Autodesk Fusion 360 part; units mm, degrees
(part 6 of 7)
extrude "Washer (3)'" add sketch "Washer (2) (3)" along normal blind 0.4 separate body makes body 75 in component "HARDWARE | PCA M2x14 · unthreaded reference"
ref_plane "WorkPlane16" through (0, 0, 22.57) normal (0, 0, 1) x (1, 0, 0) in component "HARDWARE | PCA M2x14 · unthreaded reference"
sketch "Washer clearance (2) (3)" plane through (0, 0, 22.57) normal (0, 0, 1) x (1, 0, 0) in component "HARDWARE | PCA M2x14 · unthreaded reference"
  circle A0 centre (27.94, -25.525) radius 1.2
extrude "Washer clearance (3)'" cut sketch "Washer clearance (2) (3)" along normal blind 0.4 bodies 75 in component "HARDWARE | PCA M2x14 · unthreaded reference"
ref_plane "WorkPlane17" through (0, 0, 22.97) normal (0, 0, 1) x (1, 0, 0) in component "HARDWARE | PCA M2x14 · unthreaded reference"
sketch "Hex nut (2) (3)" plane through (0, 0, 22.97) normal (0, 0, 1) x (1, 0, 0) in component "HARDWARE | PCA M2x14 · unthreaded reference"
  line L0 (30.2494, -25.525) -> (29.0947, -23.525)
  line L1 (29.0947, -23.525) -> (26.7853, -23.525)
  line L2 (26.7853, -23.525) -> (25.6306, -25.525)
  line L3 (25.6306, -25.525) -> (26.7853, -27.525)
  line L4 (26.7853, -27.525) -> (29.0947, -27.525)
  line L5 (29.0947, -27.525) -> (30.2494, -25.525)
extrude "Hex nut (3)'" add sketch "Hex nut (2) (3)" along normal blind 1.6 separate body makes body 76 in component "HARDWARE | PCA M2x14 · unthreaded reference"
ref_plane "WorkPlane18" through (0, 0, 22.97) normal (0, 0, 1) x (1, 0, 0) in component "HARDWARE | PCA M2x14 · unthreaded reference"
sketch "Nut thread envelope clearance (2) (3)" plane through (0, 0, 22.97) normal (0, 0, 1) x (1, 0, 0) in component "HARDWARE | PCA M2x14 · unthreaded reference"
  circle A0 centre (27.94, -25.525) radius 1.15
extrude "Nut thread envelope clearance (3)'" cut sketch "Nut thread envelope clearance (2) (3)" along normal blind 1.6 bodies 76 in component "HARDWARE | PCA M2x14 · unthreaded reference"
ref_plane "WorkPlane19" through (0, 0, 12) normal (0, 0, 1) x (1, 0, 0) in component "HARDWARE | PCA M2x14 · unthreaded reference"
sketch "Bolt shank (3) (3)" plane through (0, 0, 12) normal (0, 0, 1) x (1, 0, 0) in component "HARDWARE | PCA M2x14 · unthreaded reference"
  circle A0 centre (27.94, -6.475) radius 1
extrude "Bolt shank (4)'" add sketch "Bolt shank (3) (3)" along normal blind 14 separate body makes body 77 in component "HARDWARE | PCA M2x14 · unthreaded reference"
ref_plane "WorkPlane20" through (0, 0, 10) normal (0, 0, 1) x (1, 0, 0) in component "HARDWARE | PCA M2x14 · unthreaded reference"
sketch "Socket head envelope (3) (3)" plane through (0, 0, 10) normal (0, 0, 1) x (1, 0, 0) in component "HARDWARE | PCA M2x14 · unthreaded reference"
  circle A0 centre (27.94, -6.475) radius 1.9
extrude "Socket head envelope (4)'" add sketch "Socket head envelope (3) (3)" along normal blind 2 bodies 77 in component "HARDWARE | PCA M2x14 · unthreaded reference"
ref_plane "WorkPlane21" through (0, 0, 22.57) normal (0, 0, 1) x (1, 0, 0) in component "HARDWARE | PCA M2x14 · unthreaded reference"
sketch "Washer (3) (3)" plane through (0, 0, 22.57) normal (0, 0, 1) x (1, 0, 0) in component "HARDWARE | PCA M2x14 · unthreaded reference"
  circle A0 centre (27.94, -6.475) radius 2
extrude "Washer (4)'" add sketch "Washer (3) (3)" along normal blind 0.4 separate body makes body 78 in component "HARDWARE | PCA M2x14 · unthreaded reference"
ref_plane "WorkPlane22" through (0, 0, 22.57) normal (0, 0, 1) x (1, 0, 0) in component "HARDWARE | PCA M2x14 · unthreaded reference"
sketch "Washer clearance (3) (3)" plane through (0, 0, 22.57) normal (0, 0, 1) x (1, 0, 0) in component "HARDWARE | PCA M2x14 · unthreaded reference"
  circle A0 centre (27.94, -6.475) radius 1.2
extrude "Washer clearance (4)'" cut sketch "Washer clearance (3) (3)" along normal blind 0.4 bodies 78 in component "HARDWARE | PCA M2x14 · unthreaded reference"
ref_plane "WorkPlane23" through (0, 0, 22.97) normal (0, 0, 1) x (1, 0, 0) in component "HARDWARE | PCA M2x14 · unthreaded reference"
sketch "Hex nut (3) (3)" plane through (0, 0, 22.97) normal (0, 0, 1) x (1, 0, 0) in component "HARDWARE | PCA M2x14 · unthreaded reference"
  line L0 (30.2494, -6.475) -> (29.0947, -4.475)
  line L1 (29.0947, -4.475) -> (26.7853, -4.475)
  line L2 (26.7853, -4.475) -> (25.6306, -6.475)
  line L3 (25.6306, -6.475) -> (26.7853, -8.475)
  line L4 (26.7853, -8.475) -> (29.0947, -8.475)
  line L5 (29.0947, -8.475) -> (30.2494, -6.475)
extrude "Hex nut (4)'" add sketch "Hex nut (3) (3)" along normal blind 1.6 separate body makes body 79 in component "HARDWARE | PCA M2x14 · unthreaded reference"
ref_plane "WorkPlane24" through (0, 0, 22.97) normal (0, 0, 1) x (1, 0, 0) in component "HARDWARE | PCA M2x14 · unthreaded reference"
sketch "Nut thread envelope clearance (3) (3)" plane through (0, 0, 22.97) normal (0, 0, 1) x (1, 0, 0) in component "HARDWARE | PCA M2x14 · unthreaded reference"
  circle A0 centre (27.94, -6.475) radius 1.15
extrude "Nut thread envelope clearance (4)'" cut sketch "Nut thread envelope clearance (3) (3)" along normal blind 1.6 bodies 79 in component "HARDWARE | PCA M2x14 · unthreaded reference"
ref_plane "WorkPlane25" through (0, 0, 12) normal (0, 0, 1) x (1, 0, 0) in component "HARDWARE | PCA M2x14 · unthreaded reference"
sketch "Bolt shank (4) (3)" plane through (0, 0, 12) normal (0, 0, 1) x (1, 0, 0) in component "HARDWARE | PCA M2x14 · unthreaded reference"
  circle A0 centre (27.94, 25.525) radius 1
extrude "Bolt shank (5)'" add sketch "Bolt shank (4) (3)" along normal blind 14 separate body makes body 80 in component "HARDWARE | PCA M2x14 · unthreaded reference"
ref_plane "WorkPlane26" through (0, 0, 10) normal (0, 0, 1) x (1, 0, 0) in component "HARDWARE | PCA M2x14 · unthreaded reference"
sketch "Socket head envelope (4) (3)" plane through (0, 0, 10) normal (0, 0, 1) x (1, 0, 0) in component "HARDWARE | PCA M2x14 · unthreaded reference"
  circle A0 centre (27.94, 25.525) radius 1.9
extrude "Socket head envelope (5)'" add sketch "Socket head envelope (4) (3)" along normal blind 2 bodies 80 in component "HARDWARE | PCA M2x14 · unthreaded reference"
ref_plane "WorkPlane27" through (0, 0, 22.57) normal (0, 0, 1) x (1, 0, 0) in component "HARDWARE | PCA M2x14 · unthreaded reference"
sketch "Washer (4) (3)" plane through (0, 0, 22.57) normal (0, 0, 1) x (1, 0, 0) in component "HARDWARE | PCA M2x14 · unthreaded reference"
  circle A0 centre (27.94, 25.525) radius 2
extrude "Washer (5)'" add sketch "Washer (4) (3)" along normal blind 0.4 separate body makes body 81 in component "HARDWARE | PCA M2x14 · unthreaded reference"
ref_plane "WorkPlane28" through (0, 0, 22.57) normal (0, 0, 1) x (1, 0, 0) in component "HARDWARE | PCA M2x14 · unthreaded reference"
sketch "Washer clearance (4) (3)" plane through (0, 0, 22.57) normal (0, 0, 1) x (1, 0, 0) in component "HARDWARE | PCA M2x14 · unthreaded reference"
  circle A0 centre (27.94, 25.525) radius 1.2
extrude "Washer clearance (5)'" cut sketch "Washer clearance (4) (3)" along normal blind 0.4 bodies 81 in component "HARDWARE | PCA M2x14 · unthreaded reference"
ref_plane "WorkPlane29" through (0, 0, 22.97) normal (0, 0, 1) x (1, 0, 0) in component "HARDWARE | PCA M2x14 · unthreaded reference"
sketch "Hex nut (4) (3)" plane through (0, 0, 22.97) normal (0, 0, 1) x (1, 0, 0) in component "HARDWARE | PCA M2x14 · unthreaded reference"
  line L0 (30.2494, 25.525) -> (29.0947, 27.525)
  line L1 (29.0947, 27.525) -> (26.7853, 27.525)
  line L2 (26.7853, 27.525) -> (25.6306, 25.525)
  line L3 (25.6306, 25.525) -> (26.7853, 23.525)
  line L4 (26.7853, 23.525) -> (29.0947, 23.525)
  line L5 (29.0947, 23.525) -> (30.2494, 25.525)
extrude "Hex nut (5)'" add sketch "Hex nut (4) (3)" along normal blind 1.6 separate body makes body 82 in component "HARDWARE | PCA M2x14 · unthreaded reference"
ref_plane "WorkPlane30" through (0, 0, 22.97) normal (0, 0, 1) x (1, 0, 0) in component "HARDWARE | PCA M2x14 · unthreaded reference"
sketch "Nut thread envelope clearance (4) (3)" plane through (0, 0, 22.97) normal (0, 0, 1) x (1, 0, 0) in component "HARDWARE | PCA M2x14 · unthreaded reference"
  circle A0 centre (27.94, 25.525) radius 1.15
extrude "Nut thread envelope clearance (5)'" cut sketch "Nut thread envelope clearance (4) (3)" along normal blind 1.6 bodies 82 in component "HARDWARE | PCA M2x14 · unthreaded reference"
ref_plane "WorkPlane31" through (0, 0, 12) normal (0, 0, 1) x (1, 0, 0) in component "HARDWARE | PCA M2x14 · unthreaded reference"
sketch "Bolt shank (5) (2)" plane through (0, 0, 12) normal (0, 0, 1) x (1, 0, 0) in component "HARDWARE | PCA M2x14 · unthreaded reference"
  circle A0 centre (27.94, 6.475) radius 1
extrude "Bolt shank (6)'" add sketch "Bolt shank (5) (2)" along normal blind 14 separate body makes body 83 in component "HARDWARE | PCA M2x14 · unthreaded reference"
ref_plane "WorkPlane32" through (0, 0, 10) normal (0, 0, 1) x (1, 0, 0) in component "HARDWARE | PCA M2x14 · unthreaded reference"
sketch "Socket head envelope (5) (2)" plane through (0, 0, 10) normal (0, 0, 1) x (1, 0, 0) in component "HARDWARE | PCA M2x14 · unthreaded reference"
  circle A0 centre (27.94, 6.475) radius 1.9
extrude "Socket head envelope (6)'" add sketch "Socket head envelope (5) (2)" along normal blind 2 bodies 83 in component "HARDWARE | PCA M2x14 · unthreaded reference"
ref_plane "WorkPlane33" through (0, 0, 22.57) normal (0, 0, 1) x (1, 0, 0) in component "HARDWARE | PCA M2x14 · unthreaded reference"
sketch "Washer (5) (2)" plane through (0, 0, 22.57) normal (0, 0, 1) x (1, 0, 0) in component "HARDWARE | PCA M2x14 · unthreaded reference"
  circle A0 centre (27.94, 6.475) radius 2
extrude "Washer (6)'" add sketch "Washer (5) (2)" along normal blind 0.4 separate body makes body 84 in component "HARDWARE | PCA M2x14 · unthreaded reference"
ref_plane "WorkPlane34" through (0, 0, 22.57) normal (0, 0, 1) x (1, 0, 0) in component "HARDWARE | PCA M2x14 · unthreaded reference"
sketch "Washer clearance (5) (3)" plane through (0, 0, 22.57) normal (0, 0, 1) x (1, 0, 0) in component "HARDWARE | PCA M2x14 · unthreaded reference"
  circle A0 centre (27.94, 6.475) radius 1.2
extrude "Washer clearance (6)'" cut sketch "Washer clearance (5) (3)" along normal blind 0.4 bodies 84 in component "HARDWARE | PCA M2x14 · unthreaded reference"
ref_plane "WorkPlane35" through (0, 0, 22.97) normal (0, 0, 1) x (1, 0, 0) in component "HARDWARE | PCA M2x14 · unthreaded reference"
sketch "Hex nut (5) (2)" plane through (0, 0, 22.97) normal (0, 0, 1) x (1, 0, 0) in component "HARDWARE | PCA M2x14 · unthreaded reference"
  line L0 (30.2494, 6.475) -> (29.0947, 8.475)
  line L1 (29.0947, 8.475) -> (26.7853, 8.475)
  line L2 (26.7853, 8.475) -> (25.6306, 6.475)
  line L3 (25.6306, 6.475) -> (26.7853, 4.475)
  line L4 (26.7853, 4.475) -> (29.0947, 4.475)
  line L5 (29.0947, 4.475) -> (30.2494, 6.475)
extrude "Hex nut (6)'" add sketch "Hex nut (5) (2)" along normal blind 1.6 separate body makes body 85 in component "HARDWARE | PCA M2x14 · unthreaded reference"
ref_plane "WorkPlane36" through (0, 0, 22.97) normal (0, 0, 1) x (1, 0, 0) in component "HARDWARE | PCA M2x14 · unthreaded reference"
sketch "Nut thread envelope clearance (5) (3)" plane through (0, 0, 22.97) normal (0, 0, 1) x (1, 0, 0) in component "HARDWARE | PCA M2x14 · unthreaded reference"
  circle A0 centre (27.94, 6.475) radius 1.15
extrude "Nut thread envelope clearance (6)'" cut sketch "Nut thread envelope clearance (5) (3)" along normal blind 1.6 bodies 85 in component "HARDWARE | PCA M2x14 · unthreaded reference"
ref_plane "WorkPlane37" through (0, 0, 12) normal (0, 0, 1) x (1, 0, 0) in component "HARDWARE | PCA M2x14 · unthreaded reference"
sketch "Bolt shank (6) (2)" plane through (0, 0, 12) normal (0, 0, 1) x (1, 0, 0) in component "HARDWARE | PCA M2x14 · unthreaded reference"
  circle A0 centre (-27.94, 25.525) radius 1
extrude "Bolt shank (7)" add sketch "Bolt shank (6) (2)" along normal blind 14 separate body makes body 86 in component "HARDWARE | PCA M2x14 · unthreaded reference"
ref_plane "WorkPlane38" through (0, 0, 10) normal (0, 0, 1) x (1, 0, 0) in component "HARDWARE | PCA M2x14 · unthreaded reference"
sketch "Socket head envelope (6) (2)" plane through (0, 0, 10) normal (0, 0, 1) x (1, 0, 0) in component "HARDWARE | PCA M2x14 · unthreaded reference"
  circle A0 centre (-27.94, 25.525) radius 1.9
extrude "Socket head envelope (7)" add sketch "Socket head envelope (6) (2)" along normal blind 2 bodies 86 in component "HARDWARE | PCA M2x14 · unthreaded reference"
ref_plane "WorkPlane39" through (0, 0, 22.57) normal (0, 0, 1) x (1, 0, 0) in component "HARDWARE | PCA M2x14 · unthreaded reference"
sketch "Washer (6) (2)" plane through (0, 0, 22.57) normal (0, 0, 1) x (1, 0, 0) in component "HARDWARE | PCA M2x14 · unthreaded reference"
  circle A0 centre (-27.94, 25.525) radius 2
extrude "Washer (7)" add sketch "Washer (6) (2)" along normal blind 0.4 separate body makes body 87 in component "HARDWARE | PCA M2x14 · unthreaded reference"
ref_plane "WorkPlane40" through (0, 0, 22.57) normal (0, 0, 1) x (1, 0, 0) in component "HARDWARE | PCA M2x14 · unthreaded reference"
sketch "Washer clearance (6) (2)" plane through (0, 0, 22.57) normal (0, 0, 1) x (1, 0, 0) in component "HARDWARE | PCA M2x14 · unthreaded reference"
  circle A0 centre (-27.94, 25.525) radius 1.2
extrude "Washer clearance (7)" cut sketch "Washer clearance (6) (2)" along normal blind 0.4 bodies 87 in component "HARDWARE | PCA M2x14 · unthreaded reference"
ref_plane "WorkPlane41" through (0, 0, 22.97) normal (0, 0, 1) x (1, 0, 0) in component "HARDWARE | PCA M2x14 · unthreaded reference"
sketch "Hex nut (6) (2)" plane through (0, 0, 22.97) normal (0, 0, 1) x (1, 0, 0) in component "HARDWARE | PCA M2x14 · unthreaded reference"
  line L0 (-25.6306, 25.525) -> (-26.7853, 27.525)
  line L1 (-26.7853, 27.525) -> (-29.0947, 27.525)
  line L2 (-29.0947, 27.525) -> (-30.2494, 25.525)
  line L3 (-30.2494, 25.525) -> (-29.0947, 23.525)
  line L4 (-29.0947, 23.525) -> (-26.7853, 23.525)
  line L5 (-26.7853, 23.525) -> (-25.6306, 25.525)
extrude "Hex nut (7)" add sketch "Hex nut (6) (2)" along normal blind 1.6 separate body makes body 88 in component "HARDWARE | PCA M2x14 · unthreaded reference"
ref_plane "WorkPlane42" through (0, 0, 22.97) normal (0, 0, 1) x (1, 0, 0) in component "HARDWARE | PCA M2x14 · unthreaded reference"
sketch "Nut thread envelope clearance (6) (2)" plane through (0, 0, 22.97) normal (0, 0, 1) x (1, 0, 0) in component "HARDWARE | PCA M2x14 · unthreaded reference"
  circle A0 centre (-27.94, 25.525) radius 1.15
extrude "Nut thread envelope clearance (7)" cut sketch "Nut thread envelope clearance (6) (2)" along normal blind 1.6 bodies 88 in component "HARDWARE | PCA M2x14 · unthreaded reference"
ref_plane "WorkPlane43" through (0, 0, 12) normal (0, 0, 1) x (1, 0, 0) in component "HARDWARE | PCA M2x14 · unthreaded reference"
sketch "Bolt shank (7)" plane through (0, 0, 12) normal (0, 0, 1) x (1, 0, 0) in component "HARDWARE | PCA M2x14 · unthreaded reference"
  circle A0 centre (-27.94, 6.475) radius 1
extrude "Bolt shank (8)" add sketch "Bolt shank (7)" along normal blind 14 separate body makes body 89 in component "HARDWARE | PCA M2x14 · unthreaded reference"
ref_plane "WorkPlane44" through (0, 0, 10) normal (0, 0, 1) x (1, 0, 0) in component "HARDWARE | PCA M2x14 · unthreaded reference"
sketch "Socket head envelope (7)" plane through (0, 0, 10) normal (0, 0, 1) x (1, 0, 0) in component "HARDWARE | PCA M2x14 · unthreaded reference"
  circle A0 centre (-27.94, 6.475) radius 1.9
extrude "Socket head envelope (8)" add sketch "Socket head envelope (7)" along normal blind 2 bodies 89 in component "HARDWARE | PCA M2x14 · unthreaded reference"
ref_plane "WorkPlane45" through (0, 0, 22.57) normal (0, 0, 1) x (1, 0, 0) in component "HARDWARE | PCA M2x14 · unthreaded reference"
sketch "Washer (7)" plane through (0, 0, 22.57) normal (0, 0, 1) x (1, 0, 0) in component "HARDWARE | PCA M2x14 · unthreaded reference"
  circle A0 centre (-27.94, 6.475) radius 2
extrude "Washer (8)" add sketch "Washer (7)" along normal blind 0.4 separate body makes body 90 in component "HARDWARE | PCA M2x14 · unthreaded reference"
ref_plane "WorkPlane46" through (0, 0, 22.57) normal (0, 0, 1) x (1, 0, 0) in component "HARDWARE | PCA M2x14 · unthreaded reference"
sketch "Washer clearance (7)" plane through (0, 0, 22.57) normal (0, 0, 1) x (1, 0, 0) in component "HARDWARE | PCA M2x14 · unthreaded reference"
  circle A0 centre (-27.94, 6.475) radius 1.2
extrude "Washer clearance (8)" cut sketch "Washer clearance (7)" along normal blind 0.4 bodies 90 in component "HARDWARE | PCA M2x14 · unthreaded reference"
ref_plane "WorkPlane47" through (0, 0, 22.97) normal (0, 0, 1) x (1, 0, 0) in component "HARDWARE | PCA M2x14 · unthreaded reference"
sketch "Hex nut (7)" plane through (0, 0, 22.97) normal (0, 0, 1) x (1, 0, 0) in component "HARDWARE | PCA M2x14 · unthreaded reference"
  line L0 (-25.6306, 6.475) -> (-26.7853, 8.475)
  line L1 (-26.7853, 8.475) -> (-29.0947, 8.475)
  line L2 (-29.0947, 8.475) -> (-30.2494, 6.475)
  line L3 (-30.2494, 6.475) -> (-29.0947, 4.475)
  line L4 (-29.0947, 4.475) -> (-26.7853, 4.475)
  line L5 (-26.7853, 4.475) -> (-25.6306, 6.475)
extrude "Hex nut (8)" add sketch "Hex nut (7)" along normal blind 1.6 separate body makes body 91 in component "HARDWARE | PCA M2x14 · unthreaded reference"
ref_plane "WorkPlane48" through (0, 0, 22.97) normal (0, 0, 1) x (1, 0, 0) in component "HARDWARE | PCA M2x14 · unthreaded reference"
sketch "Nut thread envelope clearance (7)" plane through (0, 0, 22.97) normal (0, 0, 1) x (1, 0, 0) in component "HARDWARE | PCA M2x14 · unthreaded reference"
  circle A0 centre (-27.94, 6.475) radius 1.15
extrude "Nut thread envelope clearance (8)" cut sketch "Nut thread envelope clearance (7)" along normal blind 1.6 bodies 91 in component "HARDWARE | PCA M2x14 · unthreaded reference"
ref_plane "WorkPlane1" through (0, 0, 38) normal (0, 0, 1) x (1, 0, 0) in component "HARDWARE | Feather M2x12 · unthreaded reference"
sketch "Bolt shank (8)" plane through (0, 0, 38) normal (0, 0, 1) x (1, 0, 0) in component "HARDWARE | Feather M2x12 · unthreaded reference"
  circle A0 centre (-22.86, -8.89) radius 1
extrude "Bolt shank (1)'''''" add sketch "Bolt shank (8)" along normal blind 12 separate body makes body 92 in component "HARDWARE | Feather M2x12 · unthreaded reference"
ref_plane "WorkPlane2" through (0, 0, 36) normal (0, 0, 1) x (1, 0, 0) in component "HARDWARE | Feather M2x12 · unthreaded reference"
sketch "Socket head envelope (8)" plane through (0, 0, 36) normal (0, 0, 1) x (1, 0, 0) in component "HARDWARE | Feather M2x12 · unthreaded reference"
  circle A0 centre (-22.86, -8.89) radius 1.9
extrude "Socket head envelope (1)'''''" add sketch "Socket head envelope (8)" along normal blind 2 bodies 92 in component "HARDWARE | Feather M2x12 · unthreaded reference"
ref_plane "WorkPlane3" through (0, 0, 45.97) normal (0, 0, 1) x (1, 0, 0) in component "HARDWARE | Feather M2x12 · unthreaded reference"
sketch "Washer (8)" plane through (0, 0, 45.97) normal (0, 0, 1) x (1, 0, 0) in component "HARDWARE | Feather M2x12 · unthreaded reference"
  circle A0 centre (-22.86, -8.89) radius 2
extrude "Washer (1)'''''" add sketch "Washer (8)" along normal blind 0.4 separate body makes body 93 in component "HARDWARE | Feather M2x12 · unthreaded reference"
ref_plane "WorkPlane4" through (0, 0, 45.97) normal (0, 0, 1) x (1, 0, 0) in component "HARDWARE | Feather M2x12 · unthreaded reference"
sketch "Washer clearance (8)" plane through (0, 0, 45.97) normal (0, 0, 1) x (1, 0, 0) in component "HARDWARE | Feather M2x12 · unthreaded reference"
  circle A0 centre (-22.86, -8.89) radius 1.2
extrude "Washer clearance (1)''''''" cut sketch "Washer clearance (8)" along normal blind 0.4 bodies 93 in component "HARDWARE | Feather M2x12 · unthreaded reference"
ref_plane "WorkPlane5" through (0, 0, 46.37) normal (0, 0, 1) x (1, 0, 0) in component "HARDWARE | Feather M2x12 · unthreaded reference"
sketch "Hex nut (8)" plane through (0, 0, 46.37) normal (0, 0, 1) x (1, 0, 0) in component "HARDWARE | Feather M2x12 · unthreaded reference"
  line L0 (-20.5506, -8.89) -> (-21.7053, -6.89)
  line L1 (-21.7053, -6.89) -> (-24.0147, -6.89)
  line L2 (-24.0147, -6.89) -> (-25.1694, -8.89)
  line L3 (-25.1694, -8.89) -> (-24.0147, -10.89)
  line L4 (-24.0147, -10.89) -> (-21.7053, -10.89)
  line L5 (-21.7053, -10.89) -> (-20.5506, -8.89)
extrude "Hex nut (1)'''''" add sketch "Hex nut (8)" along normal blind 1.6 separate body makes body 94 in component "HARDWARE | Feather M2x12 · unthreaded reference"
ref_plane "WorkPlane6" through (0, 0, 46.37) normal (0, 0, 1) x (1, 0, 0) in component "HARDWARE | Feather M2x12 · unthreaded reference"
sketch "Nut thread envelope clearance (8)" plane through (0, 0, 46.37) normal (0, 0, 1) x (1, 0, 0) in component "HARDWARE | Feather M2x12 · unthreaded reference"
  circle A0 centre (-22.86, -8.89) radius 1.15
extrude "Nut thread envelope clearance (1)''''''" cut sketch "Nut thread envelope clearance (8)" along normal blind 1.6 bodies 94 in component "HARDWARE | Feather M2x12 · unthreaded reference"
ref_plane "WorkPlane7" through (0, 0, 38) normal (0, 0, 1) x (1, 0, 0) in component "HARDWARE | Feather M2x12 · unthreaded reference"
sketch "Bolt shank (1) (6)" plane through (0, 0, 38) normal (0, 0, 1) x (1, 0, 0) in component "HARDWARE | Feather M2x12 · unthreaded reference"
  circle A0 centre (-22.86, 8.89) radius 1
extrude "Bolt shank (2)'''''" add sketch "Bolt shank (1) (6)" along normal blind 12 separate body makes body 95 in component "HARDWARE | Feather M2x12 · unthreaded reference"
ref_plane "WorkPlane8" through (0, 0, 36) normal (0, 0, 1) x (1, 0, 0) in component "HARDWARE | Feather M2x12 · unthreaded reference"
sketch "Socket head envelope (1) (6)" plane through (0, 0, 36) normal (0, 0, 1) x (1, 0, 0) in component "HARDWARE | Feather M2x12 · unthreaded reference"
  circle A0 centre (-22.86, 8.89) radius 1.9
extrude "Socket head envelope (2)'''''" add sketch "Socket head envelope (1) (6)" along normal blind 2 bodies 95 in component "HARDWARE | Feather M2x12 · unthreaded reference"
ref_plane "WorkPlane9" through (0, 0, 45.97) normal (0, 0, 1) x (1, 0, 0) in component "HARDWARE | Feather M2x12 · unthreaded reference"
sketch "Washer (1) (6)" plane through (0, 0, 45.97) normal (0, 0, 1) x (1, 0, 0) in component "HARDWARE | Feather M2x12 · unthreaded reference"
  circle A0 centre (-22.86, 8.89) radius 2
extrude "Washer (2)'''''" add sketch "Washer (1) (6)" along normal blind 0.4 separate body makes body 96 in component "HARDWARE | Feather M2x12 · unthreaded reference"
ref_plane "WorkPlane10" through (0, 0, 45.97) normal (0, 0, 1) x (1, 0, 0) in component "HARDWARE | Feather M2x12 · unthreaded reference"
sketch "Washer clearance (1) (7)" plane through (0, 0, 45.97) normal (0, 0, 1) x (1, 0, 0) in component "HARDWARE | Feather M2x12 · unthreaded reference"
  circle A0 centre (-22.86, 8.89) radius 1.2
extrude "Washer clearance (2)''''''" cut sketch "Washer clearance (1) (7)" along normal blind 0.4 bodies 96 in component "HARDWARE | Feather M2x12 · unthreaded reference"
ref_plane "WorkPlane11" through (0, 0, 46.37) normal (0, 0, 1) x (1, 0, 0) in component "HARDWARE | Feather M2x12 · unthreaded reference"
sketch "Hex nut (1) (6)" plane through (0, 0, 46.37) normal (0, 0, 1) x (1, 0, 0) in component "HARDWARE | Feather M2x12 · unthreaded reference"
  line L0 (-20.5506, 8.89) -> (-21.7053, 10.89)
  line L1 (-21.7053, 10.89) -> (-24.0147, 10.89)
  line L2 (-24.0147, 10.89) -> (-25.1694, 8.89)
  line L3 (-25.1694, 8.89) -> (-24.0147, 6.89)
  line L4 (-24.0147, 6.89) -> (-21.7053, 6.89)
  line L5 (-21.7053, 6.89) -> (-20.5506, 8.89)
extrude "Hex nut (2)'''''" add sketch "Hex nut (1) (6)" along normal blind 1.6 separate body makes body 97 in component "HARDWARE | Feather M2x12 · unthreaded reference"
ref_plane "WorkPlane12" through (0, 0, 46.37) normal (0, 0, 1) x (1, 0, 0) in component "HARDWARE | Feather M2x12 · unthreaded reference"
sketch "Nut thread envelope clearance (1) (7)" plane through (0, 0, 46.37) normal (0, 0, 1) x (1, 0, 0) in component "HARDWARE | Feather M2x12 · unthreaded reference"
  circle A0 centre (-22.86, 8.89) radius 1.15
extrude "Nut thread envelope clearance (2)''''''" cut sketch "Nut thread envelope clearance (1) (7)" along normal blind 1.6 bodies 97 in component "HARDWARE | Feather M2x12 · unthreaded reference"
ref_plane "WorkPlane13" through (0, 0, 38) normal (0, 0, 1) x (1, 0, 0) in component "HARDWARE | Feather M2x12 · unthreaded reference"
sketch "Bolt shank (2) (4)" plane through (0, 0, 38) normal (0, 0, 1) x (1, 0, 0) in component "HARDWARE | Feather M2x12 · unthreaded reference"
  circle A0 centre (22.86, -8.89) radius 1
extrude "Bolt shank (3)''" add sketch "Bolt shank (2) (4)" along normal blind 12 separate body makes body 98 in component "HARDWARE | Feather M2x12 · unthreaded reference"
ref_plane "WorkPlane14" through (0, 0, 36) normal (0, 0, 1) x (1, 0, 0) in component "HARDWARE | Feather M2x12 · unthreaded reference"
sketch "Socket head envelope (2) (4)" plane through (0, 0, 36) normal (0, 0, 1) x (1, 0, 0) in component "HARDWARE | Feather M2x12 · unthreaded reference"
  circle A0 centre (22.86, -8.89) radius 1.9
extrude "Socket head envelope (3)''" add sketch "Socket head envelope (2) (4)" along normal blind 2 bodies 98 in component "HARDWARE | Feather M2x12 · unthreaded reference"
ref_plane "WorkPlane15" through (0, 0, 45.97) normal (0, 0, 1) x (1, 0, 0) in component "HARDWARE | Feather M2x12 · unthreaded reference"
sketch "Washer (2) (4)" plane through (0, 0, 45.97) normal (0, 0, 1) x (1, 0, 0) in component "HARDWARE | Feather M2x12 · unthreaded reference"
  circle A0 centre (22.86, -8.89) radius 2
extrude "Washer (3)''" add sketch "Washer (2) (4)" along normal blind 0.4 separate body makes body 99 in component "HARDWARE | Feather M2x12 · unthreaded reference"
ref_plane "WorkPlane16" through (0, 0, 45.97) normal (0, 0, 1) x (1, 0, 0) in component "HARDWARE | Feather M2x12 · unthreaded reference"
sketch "Washer clearance (2) (4)" plane through (0, 0, 45.97) normal (0, 0, 1) x (1, 0, 0) in component "HARDWARE | Feather M2x12 · unthreaded reference"
  circle A0 centre (22.86, -8.89) radius 1.2
extrude "Washer clearance (3)''" cut sketch "Washer clearance (2) (4)" along normal blind 0.4 bodies 99 in component "HARDWARE | Feather M2x12 · unthreaded reference"
ref_plane "WorkPlane17" through (0, 0, 46.37) normal (0, 0, 1) x (1, 0, 0) in component "HARDWARE | Feather M2x12 · unthreaded reference"
sketch "Hex nut (2) (4)" plane through (0, 0, 46.37) normal (0, 0, 1) x (1, 0, 0) in component "HARDWARE | Feather M2x12 · unthreaded reference"
  line L0 (25.1694, -8.89) -> (24.0147, -6.89)
  line L1 (24.0147, -6.89) -> (21.7053, -6.89)
  line L2 (21.7053, -6.89) -> (20.5506, -8.89)
  line L3 (20.5506, -8.89) -> (21.7053, -10.89)
  line L4 (21.7053, -10.89) -> (24.0147, -10.89)
  line L5 (24.0147, -10.89) -> (25.1694, -8.89)
extrude "Hex nut (3)''" add sketch "Hex nut (2) (4)" along normal blind 1.6 separate body makes body 100 in component "HARDWARE | Feather M2x12 · unthreaded reference"
ref_plane "WorkPlane18" through (0, 0, 46.37) normal (0, 0, 1) x (1, 0, 0) in component "HARDWARE | Feather M2x12 · unthreaded reference"
sketch "Nut thread envelope clearance (2) (4)" plane through (0, 0, 46.37) normal (0, 0, 1) x (1, 0, 0) in component "HARDWARE | Feather M2x12 · unthreaded reference"
  circle A0 centre (22.86, -8.89) radius 1.15
extrude "Nut thread envelope clearance (3)''" cut sketch "Nut thread envelope clearance (2) (4)" along normal blind 1.6 bodies 100 in component "HARDWARE | Feather M2x12 · unthreaded reference"
ref_plane "WorkPlane19" through (0, 0, 38) normal (0, 0, 1) x (1, 0, 0) in component "HARDWARE | Feather M2x12 · unthreaded reference"
sketch "Bolt shank (3) (4)" plane through (0, 0, 38) normal (0, 0, 1) x (1, 0, 0) in component "HARDWARE | Feather M2x12 · unthreaded reference"
  circle A0 centre (22.86, 8.89) radius 1
extrude "Bolt shank (4)''" add sketch "Bolt shank (3) (4)" along normal blind 12 separate body makes body 101 in component "HARDWARE | Feather M2x12 · unthreaded reference"
ref_plane "WorkPlane20" through (0, 0, 36) normal (0, 0, 1) x (1, 0, 0) in component "HARDWARE | Feather M2x12 · unthreaded reference"
sketch "Socket head envelope (3) (4)" plane through (0, 0, 36) normal (0, 0, 1) x (1, 0, 0) in component "HARDWARE | Feather M2x12 · unthreaded reference"
  circle A0 centre (22.86, 8.89) radius 1.9
extrude "Socket head envelope (4)''" add sketch "Socket head envelope (3) (4)" along normal blind 2 bodies 101 in component "HARDWARE | Feather M2x12 · unthreaded reference"
ref_plane "WorkPlane21" through (0, 0, 45.97) normal (0, 0, 1) x (1, 0, 0) in component "HARDWARE | Feather M2x12 · unthreaded reference"
sketch "Washer (3) (4)" plane through (0, 0, 45.97) normal (0, 0, 1) x (1, 0, 0) in component "HARDWARE | Feather M2x12 · unthreaded reference"
  circle A0 centre (22.86, 8.89) radius 2
extrude "Washer (4)''" add sketch "Washer (3) (4)" along normal blind 0.4 separate body makes body 102 in component "HARDWARE | Feather M2x12 · unthreaded reference"
ref_plane "WorkPlane22" through (0, 0, 45.97) normal (0, 0, 1) x (1, 0, 0) in component "HARDWARE | Feather M2x12 · unthreaded reference"
sketch "Washer clearance (3) (4)" plane through (0, 0, 45.97) normal (0, 0, 1) x (1, 0, 0) in component "HARDWARE | Feather M2x12 · unthreaded reference"
  circle A0 centre (22.86, 8.89) radius 1.2
extrude "Washer clearance (4)''" cut sketch "Washer clearance (3) (4)" along normal blind 0.4 bodies 102 in component "HARDWARE | Feather M2x12 · unthreaded reference"
ref_plane "WorkPlane23" through (0, 0, 46.37) normal (0, 0, 1) x (1, 0, 0) in component "HARDWARE | Feather M2x12 · unthreaded reference"
sketch "Hex nut (3) (4)" plane through (0, 0, 46.37) normal (0, 0, 1) x (1, 0, 0) in component "HARDWARE | Feather M2x12 · unthreaded reference"
  line L0 (25.1694, 8.89) -> (24.0147, 10.89)
  line L1 (24.0147, 10.89) -> (21.7053, 10.89)
  line L2 (21.7053, 10.89) -> (20.5506, 8.89)
  line L3 (20.5506, 8.89) -> (21.7053, 6.89)
  line L4 (21.7053, 6.89) -> (24.0147, 6.89)
  line L5 (24.0147, 6.89) -> (25.1694, 8.89)
extrude "Hex nut (4)''" add sketch "Hex nut (3) (4)" along normal blind 1.6 separate body makes body 103 in component "HARDWARE | Feather M2x12 · unthreaded reference"
ref_plane "WorkPlane24" through (0, 0, 46.37) normal (0, 0, 1) x (1, 0, 0) in component "HARDWARE | Feather M2x12 · unthreaded reference"
sketch "Nut thread envelope clearance (3) (4)" plane through (0, 0, 46.37) normal (0, 0, 1) x (1, 0, 0) in component "HARDWARE | Feather M2x12 · unthreaded reference"
  circle A0 centre (22.86, 8.89) radius 1.15
extrude "Nut thread envelope clearance (4)''" cut sketch "Nut thread envelope clearance (3) (4)" along normal blind 1.6 bodies 103 in component "HARDWARE | Feather M2x12 · unthreaded reference"
ref_plane "WorkPlane1" through (0, 0, -6) normal (0, 0, 1) x (1, 0, 0) in component "HARDWARE | Servo buck M2x10 · unthreaded reference"
sketch "Bolt shank (9)" plane through (0, 0, -6) normal (0, 0, 1) x (1, 0, 0) in component "HARDWARE | Servo buck M2x10 · unthreaded reference"
  circle A0 centre (-13.716, -19.431) radius 1
extrude "Bolt shank (1)''''''" add sketch "Bolt shank (9)" along normal blind 8 separate body makes body 104 in component "HARDWARE | Servo buck M2x10 · unthreaded reference"
ref_plane "WorkPlane2" through (0, 0, -8) normal (0, 0, 1) x (1, 0, 0) in component "HARDWARE | Servo buck M2x10 · unthreaded reference"
sketch "Socket head envelope (9)" plane through (0, 0, -8) normal (0, 0, 1) x (1, 0, 0) in component "HARDWARE | Servo buck M2x10 · unthreaded reference"
  circle A0 centre (-13.716, -19.431) radius 1.9
extrude "Socket head envelope (1)''''''" add sketch "Socket head envelope (9)" along normal blind 2 bodies 104 in component "HARDWARE | Servo buck M2x10 · unthreaded reference"
ref_plane "WorkPlane3" through (0, 0, 0.6) normal (0, 0, 1) x (1, 0, 0) in component "HARDWARE | Servo buck M2x10 · unthreaded reference"
sketch "Washer (9)" plane through (0, 0, 0.6) normal (0, 0, 1) x (1, 0, 0) in component "HARDWARE | Servo buck M2x10 · unthreaded reference"
  circle A0 centre (-13.716, -19.431) radius 2
extrude "Washer (1)''''''" add sketch "Washer (9)" along normal blind 0.4 separate body makes body 105 in component "HARDWARE | Servo buck M2x10 · unthreaded reference"
ref_plane "WorkPlane4" through (0, 0, 0.6) normal (0, 0, 1) x (1, 0, 0) in component "HARDWARE | Servo buck M2x10 · unthreaded reference"
sketch "Washer clearance (9)" plane through (0, 0, 0.6) normal (0, 0, 1) x (1, 0, 0) in component "HARDWARE | Servo buck M2x10 · unthreaded reference"
  circle A0 centre (-13.716, -19.431) radius 1.2
extrude "Washer clearance (1)'''''''" cut sketch "Washer clearance (9)" along normal blind 0.4 bodies 105 in component "HARDWARE | Servo buck M2x10 · unthreaded reference"
ref_plane "WorkPlane5" through (0, 0, 1) normal (0, 0, 1) x (1, 0, 0) in component "HARDWARE | Servo buck M2x10 · unthreaded reference"
sketch "Hex nut (9)" plane through (0, 0, 1) normal (0, 0, 1) x (1, 0, 0) in component "HARDWARE | Servo buck M2x10 · unthreaded reference"
  line L0 (-11.4066, -19.431) -> (-12.5613, -17.431)
  line L1 (-12.5613, -17.431) -> (-14.8707, -17.431)
  line L2 (-14.8707, -17.431) -> (-16.0254, -19.431)
  line L3 (-16.0254, -19.431) -> (-14.8707, -21.431)
  line L4 (-14.8707, -21.431) -> (-12.5613, -21.431)
  line L5 (-12.5613, -21.431) -> (-11.4066, -19.431)
extrude "Hex nut (1)''''''" add sketch "Hex nut (9)" along normal blind 1.6 separate body makes body 106 in component "HARDWARE | Servo buck M2x10 · unthreaded reference"
ref_plane "WorkPlane6" through (0, 0, 1) normal (0, 0, 1) x (1, 0, 0) in component "HARDWARE | Servo buck M2x10 · unthreaded reference"
sketch "Nut thread envelope clearance (9)" plane through (0, 0, 1) normal (0, 0, 1) x (1, 0, 0) in component "HARDWARE | Servo buck M2x10 · unthreaded reference"
  circle A0 centre (-13.716, -19.431) radius 1.15
extrude "Nut thread envelope clearance (1)'''''''" cut sketch "Nut thread envelope clearance (9)" along normal blind 1.6 bodies 106 in component "HARDWARE | Servo buck M2x10 · unthreaded reference"
ref_plane "WorkPlane7" through (0, 0, -6) normal (0, 0, 1) x (1, 0, 0) in component "HARDWARE | Servo buck M2x10 · unthreaded reference"
sketch "Bolt shank (1) (7)" plane through (0, 0, -6) normal (0, 0, 1) x (1, 0, 0) in component "HARDWARE | Servo buck M2x10 · unthreaded reference"
  circle A0 centre (11.684, -19.431) radius 1
extrude "Bolt shank (2)''''''" add sketch "Bolt shank (1) (7)" along normal blind 8 separate body makes body 107 in component "HARDWARE | Servo buck M2x10 · unthreaded reference"
ref_plane "WorkPlane8" through (0, 0, -8) normal (0, 0, 1) x (1, 0, 0) in component "HARDWARE | Servo buck M2x10 · unthreaded reference"
sketch "Socket head envelope (1) (7)" plane through (0, 0, -8) normal (0, 0, 1) x (1, 0, 0) in component "HARDWARE | Servo buck M2x10 · unthreaded reference"
  circle A0 centre (11.684, -19.431) radius 1.9
extrude "Socket head envelope (2)''''''" add sketch "Socket head envelope (1) (7)" along normal blind 2 bodies 107 in component "HARDWARE | Servo buck M2x10 · unthreaded reference"
ref_plane "WorkPlane9" through (0, 0, 0.6) normal (0, 0, 1) x (1, 0, 0) in component "HARDWARE | Servo buck M2x10 · unthreaded reference"
sketch "Washer (1) (7)" plane through (0, 0, 0.6) normal (0, 0, 1) x (1, 0, 0) in component "HARDWARE | Servo buck M2x10 · unthreaded reference"
  circle A0 centre (11.684, -19.431) radius 2
extrude "Washer (2)''''''" add sketch "Washer (1) (7)" along normal blind 0.4 separate body makes body 108 in component "HARDWARE | Servo buck M2x10 · unthreaded reference"
ref_plane "WorkPlane10" through (0, 0, 0.6) normal (0, 0, 1) x (1, 0, 0) in component "HARDWARE | Servo buck M2x10 · unthreaded reference"
sketch "Washer clearance (1) (8)" plane through (0, 0, 0.6) normal (0, 0, 1) x (1, 0, 0) in component "HARDWARE | Servo buck M2x10 · unthreaded reference"
  circle A0 centre (11.684, -19.431) radius 1.2
extrude "Washer clearance (2)'''''''" cut sketch "Washer clearance (1) (8)" along normal blind 0.4 bodies 108 in component "HARDWARE | Servo buck M2x10 · unthreaded reference"
ref_plane "WorkPlane11" through (0, 0, 1) normal (0, 0, 1) x (1, 0, 0) in component "HARDWARE | Servo buck M2x10 · unthreaded reference"
sketch "Hex nut (1) (7)" plane through (0, 0, 1) normal (0, 0, 1) x (1, 0, 0) in component "HARDWARE | Servo buck M2x10 · unthreaded reference"
  line L0 (13.9934, -19.431) -> (12.8387, -17.431)
  line L1 (12.8387, -17.431) -> (10.5293, -17.431)
  line L2 (10.5293, -17.431) -> (9.3746, -19.431)
  line L3 (9.3746, -19.431) -> (10.5293, -21.431)
  line L4 (10.5293, -21.431) -> (12.8387, -21.431)
  line L5 (12.8387, -21.431) -> (13.9934, -19.431)
extrude "Hex nut (2)''''''" add sketch "Hex nut (1) (7)" along normal blind 1.6 separate body makes body 109 in component "HARDWARE | Servo buck M2x10 · unthreaded reference"
ref_plane "WorkPlane12" through (0, 0, 1) normal (0, 0, 1) x (1, 0, 0) in component "HARDWARE | Servo buck M2x10 · unthreaded reference"
sketch "Nut thread envelope clearance (1) (8)" plane through (0, 0, 1) normal (0, 0, 1) x (1, 0, 0) in component "HARDWARE | Servo buck M2x10 · unthreaded reference"
  circle A0 centre (11.684, -19.431) radius 1.15
extrude "Nut thread envelope clearance (2)'''''''" cut sketch "Nut thread envelope clearance (1) (8)" along normal blind 1.6 bodies 109 in component "HARDWARE | Servo buck M2x10 · unthreaded reference"
ref_plane "WorkPlane13" through (0, 0, -6) normal (0, 0, 1) x (1, 0, 0) in component "HARDWARE | Servo buck M2x10 · unthreaded reference"
sketch "Bolt shank (2) (5)" plane through (0, 0, -6) normal (0, 0, 1) x (1, 0, 0) in component "HARDWARE | Servo buck M2x10 · unthreaded reference"
  circle A0 centre (-13.716, 19.431) radius 1
extrude "Bolt shank (3)'''" add sketch "Bolt shank (2) (5)" along normal blind 8 separate body makes body 110 in component "HARDWARE | Servo buck M2x10 · unthreaded reference"
ref_plane "WorkPlane14" through (0, 0, -8) normal (0, 0, 1) x (1, 0, 0) in component "HARDWARE | Servo buck M2x10 · unthreaded reference"
sketch "Socket head envelope (2) (5)" plane through (0, 0, -8) normal (0, 0, 1) x (1, 0, 0) in component "HARDWARE | Servo buck M2x10 · unthreaded reference"
  circle A0 centre (-13.716, 19.431) radius 1.9
extrude "Socket head envelope (3)'''" add sketch "Socket head envelope (2) (5)" along normal blind 2 bodies 110 in component "HARDWARE | Servo buck M2x10 · unthreaded reference"
ref_plane "WorkPlane15" through (0, 0, 0.6) normal (0, 0, 1) x (1, 0, 0) in component "HARDWARE | Servo buck M2x10 · unthreaded reference"
sketch "Washer (2) (5)" plane through (0, 0, 0.6) normal (0, 0, 1) x (1, 0, 0) in component "HARDWARE | Servo buck M2x10 · unthreaded reference"
  circle A0 centre (-13.716, 19.431) radius 2
extrude "Washer (3)'''" add sketch "Washer (2) (5)" along normal blind 0.4 separate body makes body 111 in component "HARDWARE | Servo buck M2x10 · unthreaded reference"
ref_plane "WorkPlane16" through (0, 0, 0.6) normal (0, 0, 1) x (1, 0, 0) in component "HARDWARE | Servo buck M2x10 · unthreaded reference"
sketch "Washer clearance (2) (5)" plane through (0, 0, 0.6) normal (0, 0, 1) x (1, 0, 0) in component "HARDWARE | Servo buck M2x10 · unthreaded reference"
  circle A0 centre (-13.716, 19.431) radius 1.2
extrude "Washer clearance (3)'''" cut sketch "Washer clearance (2) (5)" along normal blind 0.4 bodies 111 in component "HARDWARE | Servo buck M2x10 · unthreaded reference"
ref_plane "WorkPlane17" through (0, 0, 1) normal (0, 0, 1) x (1, 0, 0) in component "HARDWARE | Servo buck M2x10 · unthreaded reference"
sketch "Hex nut (2) (5)" plane through (0, 0, 1) normal (0, 0, 1) x (1, 0, 0) in component "HARDWARE | Servo buck M2x10 · unthreaded reference"
  line L0 (-11.4066, 19.431) -> (-12.5613, 21.431)
  line L1 (-12.5613, 21.431) -> (-14.8707, 21.431)
  line L2 (-14.8707, 21.431) -> (-16.0254, 19.431)
  line L3 (-16.0254, 19.431) -> (-14.8707, 17.431)
  line L4 (-14.8707, 17.431) -> (-12.5613, 17.431)
  line L5 (-12.5613, 17.431) -> (-11.4066, 19.431)
extrude "Hex nut (3)'''" add sketch "Hex nut (2) (5)" along normal blind 1.6 separate body makes body 112 in component "HARDWARE | Servo buck M2x10 · unthreaded reference"
ref_plane "WorkPlane18" through (0, 0, 1) normal (0, 0, 1) x (1, 0, 0) in component "HARDWARE | Servo buck M2x10 · unthreaded reference"
sketch "Nut thread envelope clearance (2) (5)" plane through (0, 0, 1) normal (0, 0, 1) x (1, 0, 0) in component "HARDWARE | Servo buck M2x10 · unthreaded reference"
  circle A0 centre (-13.716, 19.431) radius 1.15
extrude "Nut thread envelope clearance (3)'''" cut sketch "Nut thread envelope clearance (2) (5)" along normal blind 1.6 bodies 112 in component "HARDWARE | Servo buck M2x10 · unthreaded reference"
ref_plane "WorkPlane19" through (0, 0, -6) normal (0, 0, 1) x (1, 0, 0) in component "HARDWARE | Servo buck M2x10 · unthreaded reference"
sketch "Bolt shank (3) (5)" plane through (0, 0, -6) normal (0, 0, 1) x (1, 0, 0) in component "HARDWARE | Servo buck M2x10 · unthreaded reference"
  circle A0 centre (11.684, 19.431) radius 1
extrude "Bolt shank (4)'''" add sketch "Bolt shank (3) (5)" along normal blind 8 separate body makes body 113 in component "HARDWARE | Servo buck M2x10 · unthreaded reference"
ref_plane "WorkPlane20" through (0, 0, -8) normal (0, 0, 1) x (1, 0, 0) in component "HARDWARE | Servo buck M2x10 · unthreaded reference"
sketch "Socket head envelope (3) (5)" plane through (0, 0, -8) normal (0, 0, 1) x (1, 0, 0) in component "HARDWARE | Servo buck M2x10 · unthreaded reference"
  circle A0 centre (11.684, 19.431) radius 1.9
extrude "Socket head envelope (4)'''" add sketch "Socket head envelope (3) (5)" along normal blind 2 bodies 113 in component "HARDWARE | Servo buck M2x10 · unthreaded reference"
ref_plane "WorkPlane21" through (0, 0, 0.6) normal (0, 0, 1) x (1, 0, 0) in component "HARDWARE | Servo buck M2x10 · unthreaded reference"
sketch "Washer (3) (5)" plane through (0, 0, 0.6) normal (0, 0, 1) x (1, 0, 0) in component "HARDWARE | Servo buck M2x10 · unthreaded reference"
  circle A0 centre (11.684, 19.431) radius 2
extrude "Washer (4)'''" add sketch "Washer (3) (5)" along normal blind 0.4 separate body makes body 114 in component "HARDWARE | Servo buck M2x10 · unthreaded reference"
ref_plane "WorkPlane22" through (0, 0, 0.6) normal (0, 0, 1) x (1, 0, 0) in component "HARDWARE | Servo buck M2x10 · unthreaded reference"
sketch "Washer clearance (3) (5)" plane through (0, 0, 0.6) normal (0, 0, 1) x (1, 0, 0) in component "HARDWARE | Servo buck M2x10 · unthreaded reference"
  circle A0 centre (11.684, 19.431) radius 1.2
extrude "Washer clearance (4)'''" cut sketch "Washer clearance (3) (5)" along normal blind 0.4 bodies 114 in component "HARDWARE | Servo buck M2x10 · unthreaded reference"
ref_plane "WorkPlane23" through (0, 0, 1) normal (0, 0, 1) x (1, 0, 0) in component "HARDWARE | Servo buck M2x10 · unthreaded reference"
sketch "Hex nut (3) (5)" plane through (0, 0, 1) normal (0, 0, 1) x (1, 0, 0) in component "HARDWARE | Servo buck M2x10 · unthreaded reference"
  line L0 (13.9934, 19.431) -> (12.8387, 21.431)
  line L1 (12.8387, 21.431) -> (10.5293, 21.431)
  line L2 (10.5293, 21.431) -> (9.3746, 19.431)
  line L3 (9.3746, 19.431) -> (10.5293, 17.431)
  line L4 (10.5293, 17.431) -> (12.8387, 17.431)
  line L5 (12.8387, 17.431) -> (13.9934, 19.431)
extrude "Hex nut (4)'''" add sketch "Hex nut (3) (5)" along normal blind 1.6 separate body makes body 115 in component "HARDWARE | Servo buck M2x10 · unthreaded reference"
ref_plane "WorkPlane24" through (0, 0, 1) normal (0, 0, 1) x (1, 0, 0) in component "HARDWARE | Servo buck M2x10 · unthreaded reference"
sketch "Nut thread envelope clearance (3) (5)" plane through (0, 0, 1) normal (0, 0, 1) x (1, 0, 0) in component "HARDWARE | Servo buck M2x10 · unthreaded reference"
  circle A0 centre (11.684, 19.431) radius 1.15
extrude "Nut thread envelope clearance (4)'''" cut sketch "Nut thread envelope clearance (3) (5)" along normal blind 1.6 bodies 115 in component "HARDWARE | Servo buck M2x10 · unthreaded reference"
ref_plane "WorkPlane1" through (0, 0, 12) normal (0, 0, 1) x (1, 0, 0) in component "HARDWARE | Core M2x50 · unthreaded reference"
sketch "Bolt shank (10)" plane through (0, 0, 12) normal (0, 0, 1) x (1, 0, 0) in component "HARDWARE | Core M2x50 · unthreaded reference"
  circle A0 centre (36.3731, 21) radius 1
extrude "Bolt shank (1)'''''''" add sketch "Bolt shank (10)" along normal blind 50 separate body makes body 116 in component "HARDWARE | Core M2x50 · unthreaded reference"
ref_plane "WorkPlane2" through (0, 0, 10) normal (0, 0, 1) x (1, 0, 0) in component "HARDWARE | Core M2x50 · unthreaded reference"
sketch "Socket head envelope (10)" plane through (0, 0, 10) normal (0, 0, 1) x (1, 0, 0) in component "HARDWARE | Core M2x50 · unthreaded reference"
  circle A0 centre (36.3731, 21) radius 1.9
extrude "Socket head envelope (1)'''''''" add sketch "Socket head envelope (10)" along normal blind 2 bodies 116 in component "HARDWARE | Core M2x50 · unthreaded reference"
ref_plane "WorkPlane3" through (0, 0, 57.4) normal (0, 0, 1) x (1, 0, 0) in component "HARDWARE | Core M2x50 · unthreaded reference"
sketch "Washer (10)" plane through (0, 0, 57.4) normal (0, 0, 1) x (1, 0, 0) in component "HARDWARE | Core M2x50 · unthreaded reference"
  circle A0 centre (36.3731, 21) radius 2
extrude "Washer (1)'''''''" add sketch "Washer (10)" along normal blind 0.4 separate body makes body 117 in component "HARDWARE | Core M2x50 · unthreaded reference"
ref_plane "WorkPlane4" through (0, 0, 57.4) normal (0, 0, 1) x (1, 0, 0) in component "HARDWARE | Core M2x50 · unthreaded reference"
sketch "Washer clearance (10)" plane through (0, 0, 57.4) normal (0, 0, 1) x (1, 0, 0) in component "HARDWARE | Core M2x50 · unthreaded reference"
  circle A0 centre (36.3731, 21) radius 1.2
extrude "Washer clearance (1)''''''''" cut sketch "Washer clearance (10)" along normal blind 0.4 bodies 117 in component "HARDWARE | Core M2x50 · unthreaded reference"
ref_plane "WorkPlane5" through (0, 0, 57.8) normal (0, 0, 1) x (1, 0, 0) in component "HARDWARE | Core M2x50 · unthreaded reference"
sketch "Hex nut (10)" plane through (0, 0, 57.8) normal (0, 0, 1) x (1, 0, 0) in component "HARDWARE | Core M2x50 · unthreaded reference"
  line L0 (38.6825, 21) -> (37.5278, 23)
  line L1 (37.5278, 23) -> (35.2184, 23)
  line L2 (35.2184, 23) -> (34.0637, 21)
  line L3 (34.0637, 21) -> (35.2184, 19)
  line L4 (35.2184, 19) -> (37.5278, 19)
  line L5 (37.5278, 19) -> (38.6825, 21)
extrude "Hex nut (1)'''''''" add sketch "Hex nut (10)" along normal blind 1.6 separate body makes body 118 in component "HARDWARE | Core M2x50 · unthreaded reference"
ref_plane "WorkPlane6" through (0, 0, 57.8) normal (0, 0, 1) x (1, 0, 0) in component "HARDWARE | Core M2x50 · unthreaded reference"
sketch "Nut thread envelope clearance (10)" plane through (0, 0, 57.8) normal (0, 0, 1) x (1, 0, 0) in component "HARDWARE | Core M2x50 · unthreaded reference"
  circle A0 centre (36.3731, 21) radius 1.15
extrude "Nut thread envelope clearance (1)''''''''" cut sketch "Nut thread envelope clearance (10)" along normal blind 1.6 bodies 118 in component "HARDWARE | Core M2x50 · unthreaded reference"
ref_plane "WorkPlane7" through (0, 0, 12) normal (0, 0, 1) x (1, 0, 0) in component "HARDWARE | Core M2x50 · unthreaded reference"
sketch "Bolt shank (1) (8)" plane through (0, 0, 12) normal (0, 0, 1) x (1, 0, 0) in component "HARDWARE | Core M2x50 · unthreaded reference"
  circle A0 centre (0, 42) radius 1
extrude "Bolt shank (2)'''''''" add sketch "Bolt shank (1) (8)" along normal blind 50 separate body makes body 119 in component "HARDWARE | Core M2x50 · unthreaded reference"
ref_plane "WorkPlane8" through (0, 0, 10) normal (0, 0, 1) x (1, 0, 0) in component "HARDWARE | Core M2x50 · unthreaded reference"
sketch "Socket head envelope (1) (8)" plane through (0, 0, 10) normal (0, 0, 1) x (1, 0, 0) in component "HARDWARE | Core M2x50 · unthreaded reference"
  circle A0 centre (0, 42) radius 1.9
extrude "Socket head envelope (2)'''''''" add sketch "Socket head envelope (1) (8)" along normal blind 2 bodies 119 in component "HARDWARE | Core M2x50 · unthreaded reference"
ref_plane "WorkPlane9" through (0, 0, 57.4) normal (0, 0, 1) x (1, 0, 0) in component "HARDWARE | Core M2x50 · unthreaded reference"
sketch "Washer (1) (8)" plane through (0, 0, 57.4) normal (0, 0, 1) x (1, 0, 0) in component "HARDWARE | Core M2x50 · unthreaded reference"
  circle A0 centre (0, 42) radius 2
extrude "Washer (2)'''''''" add sketch "Washer (1) (8)" along normal blind 0.4 separate body makes body 120 in component "HARDWARE | Core M2x50 · unthreaded reference"
ref_plane "WorkPlane10" through (0, 0, 57.4) normal (0, 0, 1) x (1, 0, 0) in component "HARDWARE | Core M2x50 · unthreaded reference"
sketch "Washer clearance (1) (9)" plane through (0, 0, 57.4) normal (0, 0, 1) x (1, 0, 0) in component "HARDWARE | Core M2x50 · unthreaded reference"
  circle A0 centre (0, 42) radius 1.2
extrude "Washer clearance (2)''''''''" cut sketch "Washer clearance (1) (9)" along normal blind 0.4 bodies 120 in component "HARDWARE | Core M2x50 · unthreaded reference"
ref_plane "WorkPlane11" through (0, 0, 57.8) normal (0, 0, 1) x (1, 0, 0) in component "HARDWARE | Core M2x50 · unthreaded reference"